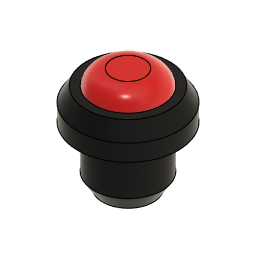
ButtonSensor (Autodesk Fusion 360 archive; units mm, degrees)
design "Button"
Autodesk Fusion 360 part; units mm, degrees
sketch "Sketch1" plane through (0, 0, 0) normal (0, 0, 1) x (1, 0, 0)
  circle A0 centre (0, 0) radius 8.75
  circle A1 centre (0, 0) radius 5.9
  dimension "d1" = 17.5
  dimension "d2" = 11.8
  constraint coincident A0.centre A1.centre
  measures "d1" diameter of A0
  measures "d2" diameter of A1
extrude "Extrude1" add sketch "Sketch1" along normal blind 10 contours A1 makes body 1
extrude "Extrude2" add sketch "Sketch1" along normal blind 15.4 and the other way blind -10 separate body contours A0 | A1 makes body 2
chamfer "Chamfer1" distance 2.5 distance2 1.5 1 edges at (-5.5007, -2.1335, 0) measured on face at (5.8927, -0.2941, 6.6667) on bodies 1
chamfer "Chamfer2" distance 1.5 distance2 2.5 1 edges at (-8.1579, -3.1641, 15.4) measured on face at (2.2113, -2.9606, 15.4) on bodies 2
sketch "Sketch3" plane through (0, 0, 0) normal (1, 0, 0) x (0, 1, 0)
  line L0 (-7.25, 15.4) -> (7.25, 15.4)
  line L1 (0, 18) -> (2.8, 18)
  line L2 (0, 15.4) -> (5.9, 15.4)
  arc A0 (5.9, 15.4) -> (2.8, 18) centre (2.8, 14.8519) ccw
  line L3 (0, 18) -> (0, 15.4)
  dimension "d14" = 2.8
  dimension "d15" = 5.9
  dimension "d16" = 2.6
  constraint horizontal L1
  constraint midpoint L0 L2.start
  constraint parallel L0 L2
  constraint tangent L1 A0
  constraint perpendicular L2 L3
  measures "d14" distance of L1.start L1.end
  measures "d15" distance of L2.start L2.end
  measures "d16" distance of L1 L2
revolve "Revolve1" add sketch "Sketch3" angle 360 about axis through (0, 0, 1.75) along (0, 0, 1) separate body makes body 3
equation "d5 = 18 mm - 2.6 mm"
equation "d15 = ( 11.8 / 2 ) * 1 mm"

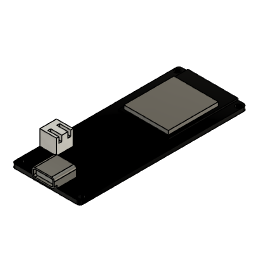
design "Firebeetle ESP32"
Autodesk Fusion 360 part; units mm, degrees
sketch "Sketch1" plane through (0, 0, 0) normal (0, 0, 1) x (1, 0, 0)
  line L0 (1, 0) -> (23.4, 0)
  line L1 (24.4, 1) -> (24.4, 59)
  line L2 (23.4, 60) -> (1, 60)
  line L3 (0, 59) -> (0, 1)
  arc A0 (24.4, 59) -> (23.4, 60) centre (23.4, 59) ccw
  arc A1 (1, 60) -> (0, 59) centre (1, 59) ccw
  arc A2 (0, 1) -> (1, 0) centre (1, 1) ccw
  arc A3 (23.4, 0) -> (24.4, 1) centre (23.4, 1) ccw
  circle A4 centre (1.2, 1.8) radius 1
  line L4 (12.2, 60) -> (12.2, 0) construction
  line L5 (0, 30) -> (24.4, 30) construction
  circle A5 centre (23.2, 1.8) radius 1
  circle A6 centre (1.2, 58.2) radius 1
  circle A7 centre (23.2, 58.2) radius 1
  point P0 (24.4, 0)
  point P1 (0, 60)
  dimension "d1" = 24.4
  dimension "d2" = 60
  dimension "d3" = 1
  dimension "d4" = 2
  dimension "d7" = 11
  dimension "d8" = 1.2
  dimension "d9" = 1.8
  constraint horizontal L0
  constraint vertical L1
  constraint horizontal L2
  constraint vertical L3
  constraint tangent L1 A0
  constraint tangent L2 A0
  constraint coincident P1 L2
  constraint coincident P1 L3
  constraint tangent L2 A1
  constraint tangent L3 A1
  constraint equal A0 A1
  constraint coincident origin L0
  constraint coincident origin L3
  constraint tangent L0 A2
  constraint tangent L3 A2
  constraint equal A0 A2
  constraint coincident P0 L0
  constraint coincident P0 L1
  constraint tangent L0 A3
  constraint tangent L1 A3
  constraint equal A0 A3
  constraint midpoint L2 L4.start
  constraint midpoint L0 L4.end
  constraint midpoint L3 L5.start
  constraint midpoint L1 L5.end
  constraint symmetric A4 L4 A5
  constraint symmetric A4 L5 A6
  constraint symmetric L5 A5 A7
  measures "d1" distance of origin P0
  measures "d2" distance of origin P1
  measures "d3" radius of A0
  measures "d4" diameter of A4
  measures "d7" distance of A4.centre L4
  measures "d8" distance of L3 A4.centre
  measures "d9" vertical distance of L0.start A4.centre
extrude "Extrude1" add sketch "Sketch1" along normal blind 1.4
sketch "Sketch2" plane through (0, 0, 1.4) normal (0, 0, 1) x (-1, 0, 0)
  circle A0 centre (-23.2, -58.2) radius 1
  circle A1 centre (-1.2, -58.2) radius 1
  circle A2 centre (-23.2, -1.8) radius 1
  circle A3 centre (-1.2, -1.8) radius 1
  arc A4 (-23.4, 0) -> (-24.4, -1) centre (-23.4, -1) ccw
  line L0 (-24.4, -1) -> (-24.4, -59)
  arc A5 (-24.4, -59) -> (-23.4, -60) centre (-23.4, -59) ccw
  line L1 (-23.4, -60) -> (-1, -60)
  arc A6 (-1, -60) -> (0, -59) centre (-1, -59) ccw
  line L2 (0, -59) -> (0, -1)
  arc A7 (0, -1) -> (-1, 0) centre (-1, -1) ccw
  line L3 (-1, 0) -> (-23.4, 0)
  line L4 (-3.2, -60) -> (-21.2, -60)
  line L5 (-21.2, -60) -> (-21.2, -35)
  line L6 (-21.2, -35) -> (-3.2, -35)
  line L7 (-3.2, -35) -> (-3.2, -60)
  line L8 (-12.2, -60) -> (-12.2, 0) construction
  dimension "d12" = 18
  dimension "d13" = 25
  dimension "d14" = 9
  constraint horizontal L4
  constraint vertical L5
  constraint horizontal L6
  constraint vertical L7
  constraint coincident L1 L4.start
  constraint midpoint L1 L8.start
  constraint midpoint L3 L8.end
  measures "d12" distance of L4.start L4.end
  measures "d13" distance of L4.start L6.end
  measures "d14" distance of L7 L8
extrude "Extrude2" add sketch "Sketch2" along normal blind 0.6 contours L1 L4 L5 L6 L7
sketch "Sketch3" plane through (0, 0, 2) normal (0, 0, 1) x (-1, 0, 0)
  line L0 (-3.2, -35) -> (-21.2, -35)
  line L1 (-21.2, -35) -> (-21.2, -60)
  line L2 (-21.2, -60) -> (-3.2, -60)
  line L3 (-3.2, -60) -> (-3.2, -35)
  line L4 (-4.2, -36) -> (-20.2, -36)
  line L5 (-20.2, -36) -> (-20.2, -54)
  line L6 (-20.2, -54) -> (-4.2, -54)
  line L7 (-4.2, -54) -> (-4.2, -36)
  dimension "d17" = 16
  dimension "d18" = 18
  dimension "d19" = 1
  dimension "d20" = 1
  constraint horizontal L4
  constraint vertical L5
  constraint horizontal L6
  constraint vertical L7
  measures "d17" distance of L4.start L4.end
  measures "d18" distance of L4.start L6.end
  measures "d19" distance of L0 L4
  measures "d20" distance of L3 L7
extrude "Extrude3" add sketch "Sketch3" along normal blind 1.4 contours L4 L5 L6 L7
sketch "Sketch4" plane through (0, 0, 1.4) normal (0, 0, 1) x (-1, 0, 0)
  line L0 (-21.2, -60) -> (-21.2, -35)
  line L1 (-21.2, -35) -> (-3.2, -35)
  line L2 (-3.2, -35) -> (-3.2, -60)
  line L3 (-3.2, -60) -> (-1, -60)
  arc A0 (-1, -60) -> (0, -59) centre (-1, -59) ccw
  line L4 (0, -59) -> (0, -1)
  arc A1 (0, -1) -> (-1, 0) centre (-1, -1) ccw
  line L5 (-1, 0) -> (-23.4, 0)
  arc A2 (-23.4, 0) -> (-24.4, -1) centre (-23.4, -1) ccw
  line L6 (-24.4, -1) -> (-24.4, -59)
  arc A3 (-24.4, -59) -> (-23.4, -60) centre (-23.4, -59) ccw
  line L7 (-23.4, -60) -> (-21.2, -60)
  circle A4 centre (-1.2, -1.8) radius 1
  circle A5 centre (-23.2, -1.8) radius 1
  circle A6 centre (-1.2, -58.2) radius 1
  circle A7 centre (-23.2, -58.2) radius 1
  line L8 (-8.2, 0) -> (-16.2, 0)
  line L9 (-16.2, 0) -> (-16.2, -7)
  line L10 (-16.2, -7) -> (-8.2, -7)
  line L11 (-8.2, -7) -> (-8.2, 0)
  line L12 (-12.2, 0) -> (-12.2, -60) construction
  line L13 (0, -16) -> (-6, -16)
  line L14 (-6, -16) -> (-6, -10)
  line L15 (-6, -10) -> (0, -10)
  line L16 (0, -10) -> (0, -16)
  dimension "d25" = 8
  dimension "d26" = 7
  dimension "d29" = 4
  dimension "d42" = 6
  dimension "d43" = 6
  dimension "d44" = 10
  constraint horizontal L8
  constraint vertical L9
  constraint horizontal L10
  constraint vertical L11
  constraint coincident L5 L8.start
  constraint midpoint L5 L12.start
  constraint perpendicular L5 L12
  constraint horizontal L13
  constraint vertical L14
  constraint horizontal L15
  constraint vertical L16
  constraint coincident L4 L13.start
  measures "d25" distance of L8.start L8.end
  measures "d26" distance of L8.start L10.end
  measures "d29" distance of L9 L12
  measures "d42" distance of L13.start L13.end
  measures "d43" distance of L13.start L15.end
  measures "d44" distance of L5 L15
extrude "Extrude4" add sketch "Sketch4" along normal blind 3.5 contours L5 L8 L9 L10 L11
fillet "Fillet1" radius 1 2 edges at (16.2, 3.5, 4.9) (8.2, 3.5, 4.9)
sketch "Sketch5" plane through (0, 0, 0) normal (0, -1, 0) x (1, 0, 0)
  arc A0 (9.2, 4.9) -> (8.2, 3.9) centre (9.2, 3.9) ccw
  line L0 (8.2, 3.9) -> (8.2, 1.4)
  line L1 (8.2, 1.4) -> (1, 1.4)
  line L2 (1, 1.4) -> (1, 0)
  line L3 (1, 0) -> (23.4, 0)
  line L4 (23.4, 0) -> (23.4, 1.4)
  line L5 (23.4, 1.4) -> (16.2, 1.4)
  line L6 (16.2, 1.4) -> (16.2, 3.9)
  arc A1 (16.2, 3.9) -> (15.2, 4.9) centre (15.2, 3.9) ccw
  line L7 (15.2, 4.9) -> (9.2, 4.9)
  line L8 (9.2, 1.4) -> (15.2, 1.4)
  line L9 (16.2, 2.4) -> (16.2, 2.65)
  arc A2 (15.2, 1.4) -> (16.2, 2.4) centre (15.2, 2.4) ccw
  line L10 (8.2, 2.4) -> (8.2, 2.65)
  arc A3 (8.2, 2.4) -> (9.2, 1.4) centre (9.2, 2.4) ccw
  arc A4 (15.7, 3.9) -> (15.2, 4.4) centre (15.2, 3.9) ccw
  line L11 (15.2, 4.4) -> (9.2, 4.4)
  arc A5 (9.2, 4.4) -> (8.7, 3.9) centre (9.2, 3.9) ccw
  line L12 (15.7, 3.9) -> (15.7, 2.4)
  line L13 (8.7, 3.9) -> (8.7, 2.4)
  line L14 (15.7, 2.4) -> (15.7, 2.65)
  arc A6 (15.2, 1.9) -> (15.7, 2.4) centre (15.2, 2.4) ccw
  line L15 (9.2, 1.9) -> (15.2, 1.9)
  arc A7 (8.7, 2.4) -> (9.2, 1.9) centre (9.2, 2.4) ccw
  line L16 (8.7, 2.4) -> (8.7, 2.65)
  dimension "d34" = 1
  dimension "d35" = 1
  dimension "d38" = -0.5
  dimension "d39" = -0.5
  constraint midpoint L6 L9.end
  constraint tangent L8 A2
  constraint midpoint L0 L10.end
  constraint tangent L8 A3
  constraint tangent L12 A6
  constraint tangent L13 A7
  measures "d34" radius of A2
  measures "d35" radius of A3
extrude "Extrude6" add sketch "Sketch5" along normal blind 1 contours A0 L0 L6 A1 L7 L8 L9 A2 L10 A3
extrude "Extrude7" add sketch "Sketch4" along normal blind 5.5 contours L4 L13 L14 L15 L16
sketch "Sketch6" plane through (0, 0, 0) normal (-1, 0, 0) x (0, -1, 0)
  line L0 (-59, 0) -> (-1, 0)
  line L1 (-1, 0) -> (-1, 1.4)
  line L2 (-1, 1.4) -> (-10, 1.4)
  line L3 (-10, 1.4) -> (-10, 6.9)
  line L4 (-10, 6.9) -> (-16, 6.9)
  line L5 (-16, 6.9) -> (-16, 1.4)
  line L6 (-16, 1.4) -> (-59, 1.4)
  line L7 (-59, 1.4) -> (-59, 0)
  line L8 (-16, 1.4) -> (-10, 1.4)
  constraint coincident L5.end L6.start
  constraint coincident L2.end L3.start
sketch "Sketch7" plane through (0, 0, 0) normal (-1, 0, 0) x (0, -1, 0)
  line L0 (-14.8, 5.7) -> (-11.2, 5.7)
  line L1 (-11.2, 5.7) -> (-11.2, 2.6)
  line L2 (-11.2, 2.6) -> (-14.8, 2.6)
  line L3 (-14.8, 2.6) -> (-14.8, 5.7)
  line L4 (-16, 6.9) -> (-16, 1.4)
  line L5 (-10, 1.4) -> (-10, 6.9)
  line L6 (-10, 6.9) -> (-16, 6.9)
  line L7 (-1, 1.4) -> (-10, 1.4)
  dimension "d47" = 1.2
  dimension "d48" = 1.2
  dimension "d49" = 1.2
  dimension "d50" = 1.2
  constraint horizontal L0
  constraint vertical L1
  constraint horizontal L2
  constraint vertical L3
  measures "d47" distance of L3 L4
  measures "d48" distance of L1 L5
  measures "d49" distance of L0 L6
  measures "d50" distance of L2 L7
extrude "Extrude8" cut sketch "Sketch7" against normal blind 4
sketch "Sketch8" plane through (0, 0, 6.9) normal (0, 0, 1) x (-1, 0, 0)
  line L0 (0, -10) -> (-6, -10)
  line L1 (-6, -10) -> (-6, -16)
  line L2 (-6, -16) -> (0, -16)
  line L3 (0, -16) -> (0, -10)
  line L4 (-6, -13) -> (0, -13) construction
  line L5 (-6, -14.1) -> (-2, -14.1)
  line L6 (-2, -14.1) -> (-2, -15.1)
  line L7 (-2, -15.1) -> (-6, -15.1)
  line L8 (-6, -15.1) -> (-6, -14.1)
  line L9 (-6, -11.9) -> (-2, -11.9)
  line L10 (-2, -10.9) -> (-6, -10.9)
  line L11 (-2, -11.9) -> (-2, -10.9)
  line L12 (-6, -10.9) -> (-6, -11.9)
  circle A0 centre (-1.2, -1.8) radius 1
  point P0 (-1, -59)
  dimension "d53" = 4
  dimension "d54" = 1
  dimension "d55" = 1.1
  dimension "d58" = 57.2
  constraint midpoint L1 L4.start
  constraint midpoint L3 L4.end
  constraint horizontal L5
  constraint vertical L6
  constraint horizontal L7
  constraint vertical L8
  constraint coincident L1 L5.start
  constraint symmetric L4 L5.start L9.start
  constraint symmetric L4 L5.end L9.end
  constraint symmetric L4 L6.end L10.start
  constraint symmetric L4 L7.end L10.end
  measures "d53" distance of L5.start L5.end
  measures "d54" distance of L5.start L7.end
  measures "d55" distance of L4 L5
  measures "d58" vertical distance of P0 A0.centre
extrude "Extrude9" cut sketch "Sketch8" against normal blind 2 contours L1 L9 L10 L11 L12 | L1 L5 L6 L7 L8

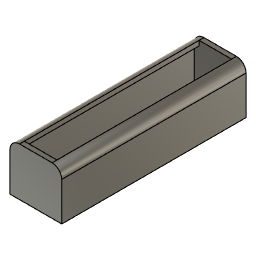
design "Battery holder"
Autodesk Fusion 360 part; units mm, degrees
sketch "Sketch1" plane through (0, 0, 0) normal (0, 0, 1) x (1, 0, 0)
  line L0 (0, 0) -> (21.5, 0)
  line L1 (21.5, 0) -> (21.5, 76.5)
  line L2 (21.5, 76.5) -> (0, 76.5)
  line L3 (0, 76.5) -> (0, 0)
  dimension "d1" = 21.5
  dimension "d2" = 76.5
  constraint horizontal L0
  constraint vertical L1
  constraint horizontal L2
  constraint vertical L3
  constraint coincident L0.start L3.end
  measures "d1" distance of L0.start L0.end
  measures "d2" distance of L0.start L2.end
extrude "Extrude1" add sketch "Sketch1" along normal blind 20 makes body 1
fillet "Fillet1" radius 4 2 edges at (0, 38.25, 20) (21.5, 38.25, 20) on bodies 1
sketch "Sketch2" plane through (0, 0, 20) normal (0, 0, 1) x (-1, 0, 0)
  line L0 (-17.5, 0) -> (-17.5, -76.5)
  line L1 (-17.5, -76.5) -> (-4, -76.5)
  line L2 (-4, -76.5) -> (-4, 0)
  line L3 (-4, 0) -> (-17.5, 0)
  line L4 (-4, -74.5) -> (-17.5, -74.5)
  line L5 (-17.5, -74.5) -> (-17.5, -2)
  line L6 (-17.5, -2) -> (-4, -2)
  line L7 (-4, -2) -> (-4, -74.5)
  dimension "d7" = 2
  dimension "d8" = 2
  constraint horizontal L4
  constraint vertical L5
  constraint horizontal L6
  constraint vertical L7
  constraint coincident L0 L5.end
  constraint coincident L2 L4.start
  measures "d7" distance of L1 L4
  measures "d8" distance of L3 L6
extrude "Extrude2" cut sketch "Sketch2" against normal blind 18 contours L0 L2 L4 L5 L6 L7 bodies 1
sketch "Sketch4" plane through (0, 2, 0) normal (0, 1, 0) x (-1, 0, 0)
  line L0 (-4, 20) -> (-17.5, 20)
  line L1 (-17.5, 20) -> (-17.5, 2)
  line L2 (-17.5, 2) -> (-4, 2)
  line L3 (-4, 2) -> (-4, 20)
  line L4 (-19.5, 2) -> (-2, 2)
  line L5 (-2, 2) -> (-2, 16)
  line L6 (-4, 18) -> (-17.5, 18)
  line L7 (-19.5, 16) -> (-19.5, 2)
  arc A0 (-17.5, 18) -> (-19.5, 16) centre (-17.5, 16) ccw
  arc A1 (-2, 16) -> (-4, 18) centre (-4, 16) ccw
  dimension "d16" = 2
  constraint horizontal L4
  constraint vertical L5
  constraint horizontal L6
  constraint vertical L7
  constraint tangent L6 A0
  constraint tangent L7 A0
  constraint tangent L5 A1
  constraint tangent L6 A1
  constraint equal A0 A1
  measures "d16" radius of A0
extrude "Extrude3" add sketch "Sketch4" along normal blind 72.5 separate body contours L3 L4 L5 A1 | L1 L2 L3 L4 L6 | L1 L4 L7 A0 makes body 2
combine "Combine1" operation cut target body 1 tool bodies 2
